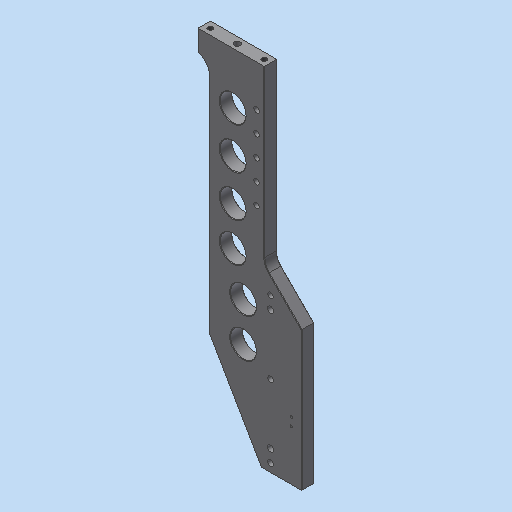
# Autodesk Inventor part: MM0937AN100_G01_122
Saved by Autodesk Inventor 2023.3 (Build 273359000, 359)
## iProperties
RuleStatus: InUse
Created: 2020-12-07
Part Number: MM0937AN100_G01_122
Material: 1.2842 90MnCrV8
Description: =<RBPARTNOTITLE2>
Document SubType Name: Modeling
Designer: RUD
Mass: 1684.07 g
Surface Area: 556.198 cm^2
Volume: 214.532 cm^3
Density: 7.85 g/cm^3
Appearance: silber AnP
AnP_Kategorie: 1
AnP_Material: =<Material>
MaxAbmaße: 12 x 337 x 100 (FM)
AnP_TemplVers: 20200821
RBDOCUMENTTYPE: DRF
RBDOCUMENTVERSION: 00
RBDRAWINGMAINSCALE: 1:1
RBDRAWINGMISSINGSPEC: --
RBDRAWINGVOLUME: --
RBDSV1: 0850
RBGBEDGESIN1: +0,5
RBGBEDGESIN2: +0,2
RBGBEDGESOUT1: -0,3
RBGBEDGESOUT2: -0,1
RBMATERIAL: =<Material>
RBMATMEETS: --
RBMATNO: =<Part Number>
RBPARTMADEOF: 12 x 337 x 100 (FM)
RBPARTNO: SIEHE MNR
RBPARTNOTITLE1: manufactured part
RBPARTNOTITLE2: Anfertigungsteil
RBPARTSAFETYINDICATOR: --
RBSURFACE: chemically nickel-coated
RBSURFACE2: chem. vernickelt
RBZEDGESNORM: ISO13715:2002-06
RBZGENDIMCLASS: m
RBZGENDIMNORM: ISO 2768-1:1989-11
RBZGENGEOCLASS: H
RBZGENGEONORM: ISO 2768-2:1989-11
RBZSURFACENORM: ISO13D2:2002-02
RBZTOLERANCENORM: ISO 14405-1:2010-12
Author: RUD
Keywords: =<RBPARTMADEOF>
Comments: =<RBSURFACE2>
Revision Number: 01
Autodesk Inventor part; units mm, degrees
ref_plane "YZ Plane" through (0, 0, 0) normal (1, 0, 0) x (0, 1, 0)
ref_plane "XZ Plane" through (0, 0, 0) normal (0, 1, 0) x (-1, 0, 0)
ref_plane "XY Plane" through (0, 0, 0) normal (0, 0, 1) x (1, 0, 0)
sketch "Skizze1" plane through (0, 0, 0) normal (0, 0, 1) x (1, 0, 0)
  line L0 (0, 404.4) -> (0, -67.4) projected
  line L1 (-94.8, 0) -> (50.8, 0) projected
  line L2 (-59, 0) -> (30, 0)
  line L3 (30, 0) -> (30, 134.7868)
  line L4 (-6, 177) -> (-6, 337)
  line L5 (-6, 337) -> (-70, 337)
  line L6 (-70, 337) -> (-70, 316.4568)
  line L7 (-59, 302) -> (-59, 0)
  arc A0 (-59, 302) -> (-70, 316.4568) centre (-74, 302) ccw
  arc A1 (-6, 177) -> (-1.6066, 166.3934) centre (9, 177) ccw
  line L8 (-1.6066, 166.3934) -> (30, 134.7868)
  dimension "d1" = 100
  dimension "d2" = 337
  dimension "d3" = 15
  dimension "d6" = 35
  dimension "d7" = 177
  dimension "d38" = 45
  dimension "d51" = 59
  dimension "d52" = 6
  dimension "d53" = 70
  constraints: 14 end point, 4 point on circle, 3 perpendicular, 3 tangent, 2 centre point, 1 collinear, 1 equal radius, 1 horizontal, 1 parallel, 1 vertical
  measures "d1" distance between parallel lines of L6 L3
  measures "d2" distance between parallel lines of L1 L5
  measures "d3" radius of A1
  measures "d6" distance from line of A0.centre L5
  measures "d7" distance from line of L1 A1.centre
  measures "d38" angle of L3 L8
  measures "d51" distance between parallel lines of L7 L0
  measures "d52" distance between parallel lines of L4 L0
  measures "d53" distance between parallel lines of L0 L6
extrude "Extrusion1" add sketch "Skizze1" along normal mid plane 12
sketch "Skizze2" plane through (0, 0, -6) normal (0, 0, 1) x (1, 0, 0)
  line L0 (0, 404.4) -> (0, -67.4) projected
  line L1 (-90, 0) -> (50, 0) projected
  line L2 (0, 8.5) -> (0, 148.5)
  point P0 (0, 78.5)
  dimension "d10" = 140
  dimension "d11" = 8.5
  constraints: 2 end point, 2 point on line, 1 coincident, 1 midpoint
  measures "d10" distance of L2.start L2.end
  measures "d11" distance from line of L1 L2.start
hole "Bohrung1" at (0, 8.5, -6) at (0, 148.5, -6) at (0, 78.5, -6) direction (0, 0, 1) diameter 5.5 end through all counterbore diameter 10 counterbore depth 5.5
sketch "Skizze3" plane through (-70, 337, 6) normal (0, 1, 0) x (1, 0, 0)
  line L0 (0, 12) -> (0, 0) projected
  line L1 (64, 12) -> (64, 0) projected
  line L2 (120, 6) -> (-20, 6) projected
  point P0 (6, 6)
  point P1 (58, 6)
  dimension "d20" = 6
  dimension "d76" = 6
  constraints: 2 point on line
  measures "d20" distance from line of L1 point (58, 6)
  measures "d76" distance from line of point (6, 6) L0
hole "Bohrung2" at (-64, 337, 0) at (-12, 337, 0) direction (0, -1, 0) diameter 4.917 depth 20 tip angle 118 thread size "M6x1" designation "M6" class "6H" standard "ISO Metric profile"
sketch "Skizze4" plane through (-70, 337, 6) normal (0, 1, 0) x (1, 0, 0)
  circle A0 centre (6, 6) radius 2.4585 projected
  circle A1 centre (58, 6) radius 2.4585 projected
  line L0 (6, 6) -> (58, 6)
  point P0 (32, 6)
  constraints: 2 end point, 1 horizontal, 1 midpoint
hole "Bohrung3" at (-38, 337, 0) direction (0, -1, 0) diameter 6 depth 12 tip angle 118
sketch "Skizze5" plane through (0, 0, 6) normal (0, 0, -1) x (-1, 0, 0)
  circle A0 centre (0, 148.5) radius 2.75 projected
  circle A1 centre (0, 8.5) radius 2.75 projected
  line L0 (0, 148.5) -> (0, 136.5)
  line L1 (0, 8.5) -> (0, 20.5)
  point P0 (0, 20.5)
  dimension "d40" = 116
  constraints: 4 end point, 2 coincident, 1 collinear, 1 point on line, 1 vertical
  measures "d40" distance of point (0, 20.5) point (0, 136.5)
hole "Bohrung4" at (0, 136.5, 6) at (0, 20.5, 6) direction (0, 0, -1) diameter 5.5 end through all counterbore diameter 6 counterbore depth 11
sketch "Skizze6" plane through (0, 0, 6) normal (0, 0, 1) x (1, 0, 0)
  line L0 (0, 404.4) -> (0, -67.4) projected
  line L1 (-90, 0) -> (50, 0) projected
  line L2 (20, 57) -> (20, 49)
  dimension "d54" = 8
  dimension "d55" = 49
  dimension "d56" = 20
  constraints: 2 coincident, 2 end point, 1 vertical
  measures "d54" distance of L2.start L2.end
  measures "d55" distance from line of L1 point (20, 49)
  measures "d56" distance from line of L0 point (20, 49)
hole "Bohrung5" at (20, 57, 6) at (20, 49, 6) direction (0, 0, -1) diameter 2.459 end through all thread size "M3x0.5" designation "M3" class "6H" standard "ISO Metric profile"
sketch "Skizze7" plane through (0, 0, -6) normal (0, -1, 0) x (-1, 0, 0)
  line L0 (0, -14.4) -> (0, 2.4) projected
  line L1 (-24, -6) -> (-9, -6)
  line L2 (-30, 0) -> (-30, -12) projected
  point P0 (-30, -6)
  dimension "d65" = 15
  dimension "d75" = 9
  constraints: 2 coincident, 2 end point, 1 horizontal, 1 horizontal alignment, 1 midpoint
  measures "d65" distance of L1.start L1.end
  measures "d75" distance from line of L0 point (-9, -6)
hole "Bohrung6" at (24, 0, 0) at (9, 0, 0) direction (0, 1, 0) diameter 4.917 depth 20 tip angle 118 thread size "M6x1" designation "M6" class "6H" standard "ISO Metric profile"
chamfer "Fase1" distance 50 angle 60 1 edges at (-59, 0, 0) measured on face at (-58.5, 0, 0)
chamfer "Fase2" distance 0.5 angle 45 9 edges at (-70, 326.7284, -6) (-70, 326.7284, 6) (-6, 257, -6) (-4.8582, 171.2597, -6) (14.1967, 150.5901, -6) (-6, 257, 6) (-4.8582, 171.2597, 6) (14.1967, 150.5901, 6) (30, 0, 0)
sketch "Skizze9" plane through (0, 0, -6) normal (0, 0, 1) x (1, 0, 0)
  line L0 (-6.5, 337) -> (-69.5, 337) projected
  line L1 (-6, 177) -> (-6, 337) projected
  point P0 (0, 0)
  point P1 (-13.5, 277)
  point P2 (-13.5, 257)
  point P3 (-13.5, 237)
  point P4 (-13.5, 217)
  point P5 (-13.5, 297)
  dimension "d89" = 20
  dimension "d90" = 20
  dimension "d91" = 20
  dimension "d93" = 120
  dimension "d101" = 20
  dimension "d106" = 7.5
  constraints: 4 vertical alignment
  measures "d89" distance of point (-13.5, 237) point (-13.5, 217)
  measures "d90" distance of point (-13.5, 257) point (-13.5, 237)
  measures "d91" distance of point (-13.5, 257) point (-13.5, 277)
  measures "d93" distance from line of L0 point (-13.5, 217)
  measures "d101" distance of point (-13.5, 277) point (-13.5, 297)
  measures "d106" distance from line of L1 point (-13.5, 297)
hole "Bohrung7" at (-13.5, 277, -6) at (-13.5, 257, -6) at (-13.5, 237, -6) at (-13.5, 217, -6) at (-13.5, 297, -6) direction (0, 0, 1) diameter 5.5 end through all counterbore diameter 10 counterbore depth 5.7 clearance for "Inbusschraube ISO 4762  versenkt" size "M5" standard "ISO"
sketch "Skizze10" plane through (0, 0, -6) normal (0, 0, -1) x (-1, 0, 0)
  circle A0 centre (13.5, 297) radius 5 projected
  line L0 (59, 86.6025) -> (59, 302) projected
  point P0 (0, 0)
  point P1 (36.5, 287)
  point P2 (36.5, 247)
  point P3 (36.5, 207)
  point P4 (36.5, 169.5)
  point P5 (26.5, 132)
  point P6 (26.5, 94.5)
  dimension "d107" = 10
  dimension "d108" = 40
  dimension "d109" = 40
  dimension "d110" = 37.5
  dimension "d118" = 37.5
  dimension "d119" = 22.5
  dimension "d120" = 37.5
  dimension "d131" = 10
  constraints: 4 vertical alignment
  measures "d107" vertical distance of point (36.5, 287) A0.centre
  measures "d108" distance of point (36.5, 247) point (36.5, 287)
  measures "d109" distance of point (36.5, 207) point (36.5, 247)
  measures "d110" distance of point (36.5, 169.5) point (36.5, 207)
  measures "d118" vertical distance of point (36.5, 169.5) point (26.5, 132)
  measures "d119" distance from line of L0 point (36.5, 287)
  measures "d120" distance of point (26.5, 132) point (26.5, 94.5)
  measures "d131" horizontal distance of point (36.5, 169.5) point (26.5, 132)
hole "Bohrung8" at (-36.5, 287, -6) at (-36.5, 247, -6) at (-36.5, 207, -6) at (-36.5, 169.5, -6) at (-26.5, 132, -6) at (-26.5, 94.5, -6) direction (0, 0, 1) diameter 25 end through all
chamfer "Fase3" distance 0.5 angle 45 22 edges at (-59, 194.3013, -6) (-61.9066, 310.8741, -6) (-59, 194.3013, 6) (-61.9066, 310.8741, 6) (-34, 43.3013, 6) (-34, 43.3013, -6) (10.25, 0, -6) (10.25, 0, 6) (30, 67.2898, 6) (30, 67.2898, -6) (-36.5, 274.5, -6) (-36.5, 274.5, 6) (-36.5, 234.5, -6) (-36.5, 234.5, 6) (-36.5, 194.5, -6) (-36.5, 194.5, 6) (-36.5, 157, -6) (-36.5, 157, 6) (-26.5, 119.5, 6) (-26.5, 119.5, -6) (-26.5, 82, 6) (-26.5, 82, -6)
equation "\"d90\" = d89"
equation "\"d91\" = d89"
equation "\"d101\" = d89"
